helga (Autodesk Fusion 360 design; units mm, degrees)
Autodesk Fusion 360 part; units mm, degrees
note: some values were not read from the file. Set by a fixed rule: which sketch regions a step uses.
sketch "Sketch1" plane through (0, 0, 0) normal (0, 1, 0) x (1, 0, 0)
  line L0 (-18.8529, -6.608) -> (-18.8529, 6.7072)
  line L1 (-18.8529, 6.7072) -> (-13.5404, 6.7072)
  line L2 (-13.5404, 6.7072) -> (-13.5404, 9.306)
  line L3 (-13.5404, 9.306) -> (-10.8692, 9.306)
  line L4 (-10.8692, 9.306) -> (-10.8692, 14.6796)
  line L5 (-10.8692, 14.6796) -> (-8.1875, 14.6796)
  line L6 (-8.1875, 14.6796) -> (-8.1875, 17.4084)
  line L7 (-8.1875, 17.4084) -> (-2.8745, 17.4084)
  line L8 (-2.8745, 17.4084) -> (-2.8745, 20.1089)
  line L9 (-2.8745, 20.1089) -> (13.211, 20.1089)
  line L10 (13.211, 20.1089) -> (13.211, 17.4084)
  line L11 (21.2891, -9.3556) -> (21.2891, -12.059)
  line L12 (21.2891, -12.059) -> (18.5792, -12.059)
  line L13 (18.5792, -12.059) -> (18.5792, -14.682)
  line L14 (18.5792, -14.682) -> (15.9015, -14.682)
  line L15 (15.9015, -14.682) -> (15.9015, -17.4193)
  line L16 (15.9015, -17.4193) -> (13.2066, -17.4193)
  line L17 (-2.8389, -17.4193) -> (-8.1595, -17.4193)
  line L18 (-10.8692, 9.306) -> (-10.8657, -14.7405)
  line L19 (-18.8529, -6.608) -> (23.8924, -6.608)
  line L20 (-13.5404, 6.7072) -> (-13.5404, -9.665)
  line L21 (21.2891, -9.3556) -> (-13.5404, -9.3556)
  line L22 (18.5792, -12.059) -> (-10.8661, -12.059)
  line L23 (15.9015, -14.682) -> (-15.6391, -14.682)
  line L24 (13.2066, -17.4193) -> (-2.8389, -17.4193)
  line L25 (-8.1875, 14.6796) -> (-8.1875, -20.5391)
  line L26 (21.2891, -9.3556) -> (21.2891, 15.6129)
  line L27 (18.5792, -12.059) -> (18.5792, 18)
  line L28 (-8.1875, 14.6796) -> (23.3304, 14.6796)
  line L29 (-2.8745, 17.4084) -> (23.633, 17.4084)
  line L30 (15.9015, -14.682) -> (15.9015, 21.5634)
  line L31 (13.2066, -17.4193) -> (13.211, 17.4084)
  line L32 (-2.8745, 17.4084) -> (-2.8745, -22)
  line L33 (13.2066, -17.4193) -> (13.2088, -20.0387)
  line L34 (13.2088, -20.0387) -> (-3.2969, -20.0524)
  line L35 (21.2891, -9.3556) -> (23.9084, -9.3556)
  line L36 (-10.8692, 9.306) -> (27.1159, 9.306)
  line L37 (23.9084, -9.3556) -> (23.9084, 10.661)
  line L38 (21.2891, 12.0886) -> (-11.4104, 12.0886)
  line L39 (-13.5404, 6.7072) -> (25.3004, 6.7072)
  line L40 (-18.8529, -3.9765) -> (23.9084, -3.9765)
  line L41 (-16.2077, -1.3461) -> (-18.8529, -1.3461)
  line L42 (-16.2077, -1.3461) -> (25.3213, -1.3461)
  line L43 (-16.166, 1.3788) -> (-18.8529, 1.3788)
  line L44 (-16.166, 1.3788) -> (24.817, 1.3788)
  line L45 (-16.144, 3.9482) -> (-18.8529, 3.9482)
  line L46 (-16.144, 3.9482) -> (24.3622, 3.9482)
  line L47 (-16.144, 3.9482) -> (-16.144, 7.2291)
  line L48 (-16.144, 3.9482) -> (-16.166, -6.9315)
  line L49 (0, 0) -> (0.0167, -20.0497)
  line L50 (0, 0) -> (0, 20.1089)
  line L51 (-5.4992, -17.4193) -> (-5.531, 17.4084)
  line L52 (2.5197, -6.608) -> (2.5309, -20.0476)
  line L53 (2.5197, -6.608) -> (2.5197, 20.1089)
  line L54 (2.5309, -20.0476) -> (5.3487, -20.0452)
  line L55 (5.3487, -20.0452) -> (5.3487, 20.1089)
  line L56 (5.3487, -20.0452) -> (8.2373, -20.0428)
  line L57 (8.2373, -20.0428) -> (8.2373, 20.1089)
  line L58 (10.5159, -3.9765) -> (10.5159, -20.0452)
  line L59 (10.5159, -3.9765) -> (10.5159, 20.1089)
  line L60 (-16.1654, -6.608) -> (-13.5404, -9.3556)
  line L61 (-13.5404, -9.3556) -> (-10.8661, -12.059)
  line L62 (-10.8657, -14.7405) -> (-8.1595, -17.4193)
  line L63 (-5.4992, -17.4193) -> (-5.4989, -17.6947)
  line L64 (-5.4992, -17.4193) -> (-2.8745, -20.0521)
  line L65 (13.2088, -20.0387) -> (15.9015, -17.4193)
  line L66 (15.9015, -17.4193) -> (18.5792, -14.682)
  line L67 (18.5792, -14.682) -> (21.2891, -12.059)
  line L68 (21.2891, -12.059) -> (23.9084, -9.3556)
  line L69 (23.9084, 9.306) -> (21.2891, 12.0886)
  line L70 (21.2891, 12.0886) -> (18.5792, 14.6796)
  line L71 (18.5792, 14.6796) -> (15.9015, 17.4084)
  line L72 (15.9015, 17.4084) -> (13.211, 20.1089)
  line L73 (-2.8745, 20.1089) -> (-5.531, 17.4084)
  line L74 (-8.1875, 17.4084) -> (-10.8692, 14.6796)
  line L75 (-10.8692, 12.0886) -> (-13.5404, 9.306)
  line L76 (-13.5404, 9.306) -> (-16.144, 6.7072)
  dimension "d6" = 31.5406
  constraint vertical L0
  constraint perpendicular L0 L1
  constraint perpendicular L1 L2
  constraint perpendicular L2 L3
  constraint perpendicular L3 L4
  constraint perpendicular L4 L5
  constraint perpendicular L5 L6
  constraint perpendicular L6 L7
  constraint perpendicular L7 L8
  constraint perpendicular L8 L9
  constraint perpendicular L9 L10
  constraint perpendicular L11 L12
  constraint perpendicular L12 L13
  constraint perpendicular L13 L14
  constraint perpendicular L14 L15
  constraint perpendicular L15 L16
  constraint perpendicular L19 L20
  constraint coincident L20 L21.end
  constraint perpendicular L20 L21
  constraint coincident L18 L22.end
  constraint perpendicular L13 L22
  constraint horizontal L23
  constraint perpendicular L17 L25
  constraint perpendicular L21 L26
  constraint perpendicular L26 L28
  constraint perpendicular L27 L29
  constraint perpendicular L29 L30
  constraint perpendicular L33 L34
  constraint perpendicular L26 L35
  constraint horizontal L36
  constraint perpendicular L36 L37
  constraint coincident L26 L38.start
  constraint perpendicular L4 L38
  constraint perpendicular L37 L39
  constraint coincident L0 L40.start
  constraint coincident L37 L40.end
  constraint perpendicular L37 L40
  constraint coincident L0 L41.end
  constraint perpendicular L0 L41
  constraint perpendicular L37 L42
  constraint coincident L0 L43.end
  constraint perpendicular L0 L43
  constraint perpendicular L37 L44
  constraint coincident L0 L45.end
  constraint perpendicular L0 L45
  constraint perpendicular L37 L46
  constraint perpendicular L1 L47
  constraint coincident L49.start L50.start
  constraint coincident L34 L49.end
  constraint perpendicular L34 L49
  constraint coincident L9 L50.end
  constraint perpendicular L9 L50
  constraint midpoint L17 L51.start
  constraint midpoint L7 L51.end
  constraint midpoint L19 L52.start
  constraint coincident L34 L52.end
  constraint perpendicular L34 L52
  constraint coincident L9 L53.end
  constraint perpendicular L9 L53
  constraint coincident L34 L54.end
  constraint coincident L9 L55.end
  constraint perpendicular L9 L55
  constraint coincident L34 L56.end
  constraint parallel L34 L56
  constraint coincident L9 L57.end
  constraint perpendicular L9 L57
  constraint coincident L40 L58.start
  constraint perpendicular L24 L58
  constraint coincident L9 L59.end
  constraint perpendicular L9 L59
  constraint coincident L48 L60.start
  constraint coincident L19 L60.start
  constraint coincident L34 L64.end
  constraint coincident L32 L64.end
  constraint coincident L36 L69.start
  constraint coincident L37 L69.start
  constraint coincident L28 L70.end
  constraint coincident L27 L70.end
  constraint coincident L30 L71.end
  constraint coincident L29 L71.end
  constraint coincident L4 L75.start
  constraint coincident L38 L75.start
  constraint coincident L47 L76.end
  constraint coincident L1 L76.end
  measures "d6" distance of L14.end L23.end
extrude "Extrude1" add sketch "Sketch1" along normal blind 5 contours L0 L19 L40 L48 | L0 L40 L41 L42 L48 | L19 L20 L40 L48 | L19 L20 L60 | L0 L41 L42 L43 L44 L48 | L18 L19 L20 L40 | L18 L19 L20 L21 | L18 L21 L61 | L0 L43 L44 L45 L48 | L20 L42 L44 L48 | L18 L21 L22 L25 | L18 L22 L23 L25 | L0 L1 L45 L47 | L18 L20 L42 L44 | L18 L23 L25 L62 | L1 L20 L46 L47 | L17 L23 L25 L51 L62 | L1 L2 L76 | L18 L20 L39 L46 | L17 L23 L32 L51 | L2 L3 L18 L39 | L3 L4 L75 | L17 L32 L64 | L4 L25 L36 L38 | L4 L5 L25 L38 | L40 L42 L49 L53 | L19 L40 L53 L55 | L17 L24 L32 L34 L49 | L5 L6 L74 | L42 L44 L49 L50 L53 | L40 L42 L53 L55 | L19 L40 L55 L57 | L24 L34 L49 L52 | L6 L7 L28 L51 | L44 L46 L50 L53 | L42 L44 L53 L55 | L40 L42 L55 L57 | L19 L40 L57 L58 | L24 L34 L52 L54 L55 | L7 L28 L32 L51 | L7 L8 L73 | L44 L46 L53 L55 | L42 L44 L55 L57 | L40 L42 L57 L59 | L19 L31 L40 L58 | L19 L21 L31 L58 | L21 L22 L31 L58 | L24 L34 L55 L56 L57 | L8 L9 L29 L50 | L39 L46 L53 L55 | L44 L46 L55 L57 | L42 L44 L57 L59 | L19 L30 L31 L40 | L24 L34 L57 L58 | L9 L29 L50 L53 | L39 L46 L55 L57 | L44 L46 L57 L59 | L31 L42 L44 L59 | L30 L31 L40 L42 | L15 L16 L23 L31 | L24 L33 L34 L58 | L13 L14 L22 L30 | L9 L29 L53 L55 | L39 L46 L57 L59 | L30 L31 L42 L44 | L11 L12 L21 L27 | L14 L15 L66 | L16 L33 L65 | L12 L13 L67 | L9 L29 L55 L57 | L31 L39 L46 L59 | L30 L31 L44 L46 | L26 L35 L37 L40 | L11 L35 L68 | L31 L36 L39 L59 | L31 L36 L38 L59 | L9 L29 L57 L59 | L30 L31 L39 L46 | L26 L37 L40 L42 | L9 L10 L29 L59 | L26 L37 L42 L44 | L28 L29 L30 L31 | L10 L29 L72 | L27 L28 L30 L38 | L26 L37 L44 L46 | L26 L27 L36 L38 | L28 L30 L71 | L27 L38 L70 | L26 L37 L39 L46 | L26 L36 L37 L39 | L26 L36 L69 makes body 1 at (-13.5244, 0, 6.6467) makes body 2 at (5.1851, 0, 0.4581)
sketch "Sketch2" plane through (0, 5, 0) normal (0, 1, 0) x (-1, 0, 0)
  line L0 (10.8684, -3.9482) -> (10.8692, -9.306)
  line L1 (10.8692, -9.306) -> (8.1875, -9.306)
  line L2 (8.1875, -9.306) -> (8.1875, -14.6796)
  line L3 (8.1875, -14.6796) -> (2.8745, -14.6796)
  line L4 (2.8745, -14.6796) -> (2.8745, -17.4084)
  line L5 (2.8745, -17.4084) -> (-13.211, -17.4084)
  line L6 (-13.211, -17.4084) -> (-13.2106, -14.6796)
  line L7 (-13.2106, -14.6796) -> (-15.9015, -14.6796)
  line L8 (-15.9015, -14.6796) -> (-15.9015, -12.0886)
  line L9 (-15.9015, -12.0886) -> (-18.5792, -12.0886)
  line L10 (-18.5792, -12.0886) -> (-18.5792, -9.306)
  line L11 (-18.5792, -9.306) -> (-21.2891, -9.306)
  line L12 (-21.2891, -9.306) -> (-21.2891, 9.3556)
  line L13 (-21.2891, 9.3556) -> (-18.5792, 9.3556)
  line L14 (-18.5792, 9.3556) -> (-18.5792, 12.059)
  line L15 (-18.5792, 12.059) -> (-15.9015, 12.059)
  line L16 (-15.9015, 12.059) -> (-15.9015, 14.682)
  line L17 (-15.9015, 14.682) -> (-13.207, 14.682)
  line L18 (-13.207, 14.682) -> (-13.2066, 17.4193)
  line L19 (-13.2066, 17.4193) -> (2.8745, 17.4193)
  line L20 (2.8745, 17.4193) -> (2.8745, 14.682)
  line L21 (2.8745, 14.682) -> (8.1875, 14.682)
  line L22 (8.1875, 14.682) -> (8.1875, 9.3556)
  line L23 (8.1875, 9.3556) -> (10.8665, 9.3556)
  line L24 (10.8665, 9.3556) -> (10.8673, 3.9765)
  line L25 (10.8673, 3.9765) -> (16.16, 3.9765)
  line L26 (16.16, 3.9765) -> (16.1547, 1.3461)
  line L27 (16.1547, 1.3461) -> (10.8676, 1.3461)
  line L28 (10.8676, 1.3461) -> (10.868, -1.3788)
  line L29 (10.868, -1.3788) -> (16.1492, -1.3788)
  line L30 (16.1492, -1.3788) -> (16.144, -3.9482)
  line L31 (16.144, -3.9482) -> (10.8684, -3.9482)
  line L32 (10.8692, -12.0886) -> (13.5404, -9.306)
  line L33 (13.5404, -9.306) -> (16.144, -6.7072)
  line L34 (16.144, -6.7072) -> (18.8529, -6.7072)
  line L35 (18.8529, -6.7072) -> (18.8529, 6.608)
  line L36 (18.8529, 6.608) -> (16.1654, 6.608)
  line L37 (16.1654, 6.608) -> (13.5404, 9.3556)
  line L38 (13.5404, 9.3556) -> (10.8661, 12.059)
  line L39 (10.8661, 12.059) -> (10.8657, 14.7405)
  line L40 (10.8657, 14.7405) -> (8.1595, 17.4193)
  line L41 (8.1595, 17.4193) -> (5.4992, 17.4193)
  line L42 (5.4992, 17.4193) -> (2.8745, 20.0521)
  line L43 (2.8745, 20.0521) -> (-13.2088, 20.0387)
  line L44 (-13.2088, 20.0387) -> (-15.9015, 17.4193)
  line L45 (-15.9015, 17.4193) -> (-18.5792, 14.682)
  line L46 (-18.5792, 14.682) -> (-21.2891, 12.059)
  line L47 (-21.2891, 12.059) -> (-23.9084, 9.3556)
  line L48 (-23.9084, 9.3556) -> (-23.9084, -9.306)
  line L49 (-23.9084, -9.306) -> (-21.2891, -12.0886)
  line L50 (-21.2891, -12.0886) -> (-18.5792, -14.6796)
  line L51 (-18.5792, -14.6796) -> (-15.9015, -17.4084)
  line L52 (-15.9015, -17.4084) -> (-13.211, -20.1089)
  line L53 (-13.211, -20.1089) -> (2.8745, -20.1089)
  line L54 (2.8745, -20.1089) -> (5.531, -17.4084)
  line L55 (5.531, -17.4084) -> (8.1875, -17.4084)
  line L56 (8.1875, -17.4084) -> (10.8692, -14.6796)
  line L57 (10.8692, -14.6796) -> (10.8692, -12.0886)
  line L58 (18.8529, -6.7072) -> (16.144, -6.7072)
  line L59 (16.144, -6.7072) -> (10.8692, -12.0886)
  line L60 (10.8692, -12.0886) -> (10.8692, -14.6796)
  line L61 (10.8692, -14.6796) -> (8.1875, -17.4084)
  line L62 (8.1875, -17.4084) -> (5.531, -17.4084)
  line L63 (5.531, -17.4084) -> (2.8745, -20.1089)
  line L64 (2.8745, -20.1089) -> (-13.211, -20.1089)
  line L65 (-13.211, -20.1089) -> (-23.9084, -9.306)
  line L66 (-23.9084, -9.306) -> (-23.9084, 9.3556)
  line L67 (-23.9084, 9.3556) -> (-13.2088, 20.0387)
  line L68 (-13.2088, 20.0387) -> (2.8745, 20.0521)
  line L69 (2.8745, 20.0521) -> (5.4992, 17.4193)
  line L70 (5.4992, 17.4193) -> (8.1595, 17.4193)
  line L71 (10.8657, 14.7405) -> (8.1595, 17.4193)
  line L72 (10.8657, 14.7405) -> (10.8661, 12.059)
  line L73 (10.8661, 12.059) -> (16.1654, 6.608)
  line L74 (16.1654, 6.608) -> (18.8529, 6.608)
  line L75 (18.8529, 6.608) -> (18.8529, -6.7072)
  constraint coincident L34.end L35.start
  constraint coincident L33.end L34.start
  constraint coincident L32.start L57.end
  constraint coincident L56.end L57.start
  constraint coincident L55.end L56.start
  constraint coincident L54.end L55.start
  constraint coincident L53.end L54.start
  constraint coincident L52.end L53.start
  constraint coincident L48.end L49.start
  constraint coincident L47.end L48.start
  constraint coincident L43.end L44.start
  constraint coincident L42.end L43.start
  constraint coincident L41.end L42.start
  constraint coincident L40.end L41.start
  constraint coincident L39.end L40.start
  constraint coincident L38.end L39.start
  constraint coincident L36.end L37.start
  constraint coincident L35.end L36.start
sketch "Sketch3" plane through (0, 0, -3.9482) normal (0, 0, 1) x (1, 0, 0)
  line L0 (10.5159, 0) -> (13.2093, 0)
  line L1 (13.2093, 0) -> (13.2093, 5)
  line L2 (13.2093, 5) -> (10.5159, 5)
  line L3 (10.5159, 5) -> (10.5159, 0)
extrude "Extrude2" cut sketch "Sketch3" along normal blind 0.7 bodies 2
sketch "Sketch4" plane through (0, 0, 0) normal (0, -1, 0) x (1, 0, 0)
  line L0 (13.2093, -3.2482) -> (13.2093, -3.9482)
  line L1 (13.2093, -3.9482) -> (10.5159, -3.9482)
  line L2 (10.5159, -3.9482) -> (10.5159, -1.3788)
  line L3 (10.5159, -1.3788) -> (13.209, -1.3788)
  line L4 (13.209, -1.3788) -> (13.2092, -3.2482)
  line L5 (13.2092, -3.2482) -> (13.2093, -3.2482)
  line L6 (13.2083, 3.9765) -> (13.2086, 1.3461)
  line L7 (13.2086, 1.3461) -> (10.5159, 1.3461)
  line L8 (10.5159, 1.3461) -> (10.5159, 3.9765)
  line L9 (10.5159, 3.9765) -> (13.2083, 3.9765)
  line L10 (0.0033, 3.9765) -> (0, 0)
  line L11 (0, 0) -> (0, -3.9482)
  line L12 (0, -3.9482) -> (2.5197, -3.9482)
  line L13 (2.5197, -3.9482) -> (2.5197, -6.7072)
  line L14 (2.5197, -6.7072) -> (10.5159, -6.7072)
  line L15 (10.5159, -6.7072) -> (10.5159, -12.0886)
  line L16 (10.5159, -12.0886) -> (13.2103, -12.0886)
  line L17 (13.2103, -12.0886) -> (13.2096, -6.7072)
  line L18 (13.2096, -6.7072) -> (15.9015, -6.7072)
  line L19 (15.9015, -6.7072) -> (15.9015, 6.608)
  line L20 (15.9015, 6.608) -> (13.208, 6.608)
  line L21 (13.208, 6.608) -> (13.2073, 12.059)
  line L22 (13.2073, 12.059) -> (10.5159, 12.059)
  line L23 (10.5159, 12.059) -> (10.5159, 6.608)
  line L24 (10.5159, 6.608) -> (2.5197, 6.608)
  line L25 (2.5197, 6.608) -> (2.5197, 3.9765)
  line L26 (2.5197, 3.9765) -> (0.0033, 3.9765)
  line L27 (11.8621, 3.9765) -> (11.8623, 1.3461)
  line L28 (10.5159, 2.6613) -> (13.2085, 2.6613)
  line L29 (10.5159, -2.6635) -> (13.2091, -2.6486)
  line L30 (11.8625, -1.3788) -> (11.8626, -3.9482)
  line L31 (14.3625, -4.6561) -> (9.3625, -4.6561)
  line L32 (9.3625, -4.6561) -> (9.3625, -0.6561)
  line L33 (9.3625, -0.6561) -> (14.3625, -0.6561)
  line L34 (14.3625, -0.6561) -> (14.3625, -4.6561)
  line L35 (14.3625, -4.6561) -> (9.3625, -0.6561) construction
  line L36 (9.3625, -4.6561) -> (14.3625, -0.6561) construction
  line L37 (14.3622, 0.6613) -> (9.3622, 0.6613)
  line L38 (9.3622, 0.6613) -> (9.3622, 4.6613)
  line L39 (9.3622, 4.6613) -> (14.3622, 4.6613)
  line L40 (14.3622, 4.6613) -> (14.3622, 0.6613)
  line L41 (14.3622, 0.6613) -> (9.3622, 4.6613) construction
  line L42 (9.3622, 0.6613) -> (14.3622, 4.6613) construction
  point P0 (11.8625, -2.6561)
  point P1 (11.8622, 2.6613)
  point P2 (11.8625, -2.6561)
  point P3 (11.8622, 2.6613)
  dimension "d22" = 5
  dimension "d23" = 4
  dimension "d24" = 5
  dimension "d25" = 4
  constraint midpoint L9 L27.start
  constraint midpoint L7 L27.end
  constraint midpoint L8 L28.start
  constraint midpoint L6 L28.end
  constraint midpoint L2 L29.start
  constraint coincident L4 L29.end
  constraint midpoint L3 L30.start
  constraint midpoint L1 L30.end
  constraint midpoint L29 P2
  constraint midpoint L27 P3
  constraint perpendicular L31 L32
  constraint parallel L31 L33
  constraint parallel L32 L34
  constraint horizontal L31
  constraint coincident L35 P2
  constraint coincident L36 P2
  constraint coincident P2 P0
  constraint perpendicular L37 L38
  constraint parallel L37 L39
  constraint parallel L38 L40
  constraint horizontal L37
  constraint coincident L41 P3
  constraint coincident L42 P3
  constraint coincident P3 P1
  measures "d22" distance of L32.end L33.end
  measures "d23" distance of L31.end L32.end
  measures "d24" distance of L38.end L39.end
  measures "d25" distance of L37.end L38.end
sketch "Sketch5" plane through (0, 5, 0) normal (0, 1, 0) x (-1, 0, 0)
  line L0 (-13.2093, -3.2482) -> (-13.2092, -3.2482)
  line L1 (-13.2092, -3.2482) -> (-13.209, -1.3788)
  line L2 (-13.209, -1.3788) -> (-10.5159, -1.3788)
  line L3 (-10.5159, -1.3788) -> (-10.5159, -3.9482)
  line L4 (-10.5159, -3.9482) -> (-13.2093, -3.9482)
  line L5 (-13.2093, -3.9482) -> (-13.2093, -3.2482)
  line L6 (-13.2086, 1.3461) -> (-13.2083, 3.9765)
  line L7 (-13.2083, 3.9765) -> (-10.5159, 3.9765)
  line L8 (-10.5159, 3.9765) -> (-10.5159, 1.3461)
  line L9 (-10.5159, 1.3461) -> (-13.2086, 1.3461)
  line L10 (0, 0) -> (-0.0033, 3.9765)
  line L11 (-0.0033, 3.9765) -> (-2.5197, 3.9765)
  line L12 (-2.5197, 3.9765) -> (-2.5197, 6.608)
  line L13 (-2.5197, 6.608) -> (-10.5159, 6.608)
  line L14 (-10.5159, 6.608) -> (-10.5159, 12.059)
  line L15 (-10.5159, 12.059) -> (-13.2073, 12.059)
  line L16 (-13.2073, 12.059) -> (-13.208, 6.608)
  line L17 (-13.208, 6.608) -> (-15.9015, 6.608)
  line L18 (-15.9015, 6.608) -> (-15.9015, -6.7072)
  line L19 (-15.9015, -6.7072) -> (-13.2096, -6.7072)
  line L20 (-13.2096, -6.7072) -> (-13.2103, -12.0886)
  line L21 (-13.2103, -12.0886) -> (-10.5159, -12.0886)
  line L22 (-10.5159, -12.0886) -> (-10.5159, -6.7072)
  line L23 (-10.5159, -6.7072) -> (-2.5197, -6.7072)
  line L24 (-2.5197, -6.7072) -> (-2.5197, -3.9482)
  line L25 (-2.5197, -3.9482) -> (0, -3.9482)
  line L26 (0, -3.9482) -> (0, 0)
loft "Loft1" cut profiles "Sketch5", "Sketch4" section 1 contours L1 L2 L3 L4 L5 section 2 contours L0 L1 L4 L29 L30 | L3 L4 L29 L30 | L1 L2 L29 L30 | L2 L3 L29 L30 | L31 L32 L33 L34 bodies 2
loft "Loft2" cut profiles "Sketch5", "Sketch4" section 1 contours L6 L7 L8 L9 section 2 contours L6 L9 L27 L28 | L6 L7 L27 L28 | L8 L9 L27 L28 | L7 L8 L27 L28 | L37 L38 L39 L40 bodies 2
sketch "Sketch6" plane through (0, 0, 0) normal (0, -1, 0) x (1, 0, 0)
  line L0 (-13.5404, -9.306) -> (-10.8692, -12.0886)
  line L1 (-10.8692, -12.0886) -> (-10.8692, -14.6796)
  line L2 (-10.8692, -14.6796) -> (-8.1875, -17.4084)
  line L3 (-8.1875, -17.4084) -> (-5.531, -17.4084)
  line L4 (-5.531, -17.4084) -> (-2.8745, -20.1089)
  line L5 (-2.8745, -20.1089) -> (13.211, -20.1089)
  line L6 (13.211, -20.1089) -> (15.9015, -17.4084)
  line L7 (15.9015, -17.4084) -> (18.5792, -14.6796)
  line L8 (18.5792, -14.6796) -> (21.2891, -12.0886)
  line L9 (21.2891, -12.0886) -> (23.9084, -9.306)
  line L10 (23.9084, 9.3556) -> (21.2891, 12.059)
  line L11 (21.2891, 12.059) -> (18.5792, 14.682)
  line L12 (18.5792, 14.682) -> (15.9015, 17.4193)
  line L13 (15.9015, 17.4193) -> (13.2088, 20.0387)
  line L14 (13.2088, 20.0387) -> (-2.8745, 20.0521)
  line L15 (-2.8745, 20.0521) -> (-5.4992, 17.4193)
  line L16 (-5.4992, 17.4193) -> (-8.1595, 17.4193)
  line L17 (-8.1595, 17.4193) -> (-10.8657, 14.7405)
  line L18 (-10.8657, 14.7405) -> (-10.8661, 12.059)
  line L19 (-10.8661, 12.059) -> (-13.5404, 9.3556)
  line L20 (-13.5404, 9.3556) -> (-16.1654, 6.608)
  line L21 (-16.1654, 6.608) -> (-18.8529, 6.608)
  line L22 (-18.8529, -6.7072) -> (-16.144, -6.7072)
  line L23 (-16.144, -6.7072) -> (-13.5404, -9.306)
  line L24 (-18.8529, 6.608) -> (-16.1654, 6.608)
  line L25 (-16.1654, 6.608) -> (-10.8661, 12.059)
  line L26 (-10.8661, 12.059) -> (-10.8657, 14.7405)
  line L27 (-10.8657, 14.7405) -> (-8.1595, 17.4193)
  line L28 (-8.1595, 17.4193) -> (-5.4992, 17.4193)
  line L29 (-5.4992, 17.4193) -> (-2.8745, 20.0521)
  line L30 (-2.8745, 20.0521) -> (13.2088, 20.0387)
  line L31 (13.2088, 20.0387) -> (23.9084, 9.3556)
  line L32 (23.9084, -9.306) -> (13.211, -20.1089)
  line L33 (13.211, -20.1089) -> (-2.8745, -20.1089)
  line L34 (-2.8745, -20.1089) -> (-5.531, -17.4084)
  line L35 (-5.531, -17.4084) -> (-8.1875, -17.4084)
  line L36 (-8.1875, -17.4084) -> (-10.8692, -14.6796)
  line L37 (-10.8692, -14.6796) -> (-10.8692, -12.0886)
  line L38 (-10.8692, -12.0886) -> (-16.144, -6.7072)
  line L39 (-16.144, -6.7072) -> (-18.8529, -6.7072)
  line L40 (9.8625, -1.1561) -> (9.8625, -4.1561)
  line L41 (9.8625, -4.1561) -> (13.8625, -4.1561)
  line L42 (13.8625, -4.1561) -> (13.8625, -1.1561)
  line L43 (13.8625, -1.1561) -> (9.8625, -1.1561)
  line L44 (9.8622, 4.1613) -> (9.8622, 1.1613)
  line L45 (9.8622, 1.1613) -> (13.8622, 1.1613)
  line L46 (13.8622, 1.1613) -> (13.8622, 4.1613)
  line L47 (13.8622, 4.1613) -> (9.8622, 4.1613)
  line L48 (23.9084, 9.3556) -> (33.9084, 9.3556)
  line L49 (33.9084, 9.3556) -> (33.9084, -9.306)
  line L50 (33.9084, -9.306) -> (23.9084, -9.306)
  line L51 (-18.8529, 6.608) -> (-28.8529, 6.608)
  line L52 (-18.8529, -6.7072) -> (-28.8529, -6.7072)
  line L53 (-28.8529, 6.608) -> (-28.8529, -6.7072)
  point P0 (9.8625, -1.1561)
  point P1 (9.8625, -4.1561)
  point P2 (13.8625, -4.1561)
  point P3 (13.8625, -4.1561)
  point P4 (13.8625, -1.1561)
  point P5 (9.8622, 4.1613)
  point P6 (9.8622, 1.1613)
  point P7 (13.8622, 1.1613)
  point P8 (13.8622, 4.1613)
  dimension "d17" = 10
  dimension "d20" = 10
  dimension "d21" = 10
  constraint coincident L21.end L24.start
  constraint coincident L20.end L21.start
  constraint coincident L18.end L19.start
  constraint coincident L17.end L18.start
  constraint coincident L16.end L17.start
  constraint coincident L15.end L16.start
  constraint coincident L14.end L15.start
  constraint coincident L13.end L14.start
  constraint coincident L10.start L31.end
  constraint coincident L9.end L32.start
  constraint coincident L5.end L6.start
  constraint coincident L4.end L5.start
  constraint coincident L3.end L4.start
  constraint coincident L2.end L3.start
  constraint coincident L1.end L2.start
  constraint coincident L0.end L1.start
  constraint coincident L22.end L23.start
  constraint coincident L22.start L39.end
  constraint coincident P0 L40.start
  constraint coincident P1 L40.end
  constraint coincident P3 P2
  constraint coincident P4 L42.end
  constraint coincident P5 L44.start
  constraint coincident P6 L44.end
  constraint coincident P7 L45.end
  constraint coincident P8 L46.end
  constraint horizontal L48
  constraint vertical L49
  constraint horizontal L50
  constraint horizontal L51
  constraint perpendicular L52 L53
  measures "d17" distance of L10.start L48.end
  measures "d20" distance of L21.end L51.end
  measures "d21" distance of L22.start L52.end
chamfer "Chamfer2" distance 0.7 angle 45 17 edges at (6.5178, 5, -6.7072) (2.5197, 5, -5.3277) (1.2599, 5, -3.9482) (0, 5, -1.9741) (0.0017, 5, 1.9883) (1.2615, 5, 3.9765) (2.5197, 5, 5.2922) (6.5178, 5, 6.608) (10.5159, 5, 9.3335) (11.8616, 5, 12.059) (13.2076, 5, 9.3335) (14.5547, 5, 6.608) (15.9015, 5, -0.0496) (14.5556, 5, -6.7072) (13.21, 5, -9.3979) (10.5159, 5, -9.3979) (11.8631, 5, -12.0886) on bodies 2
chamfer "Chamfer3" distance 0.7 angle 45 59 edges at (-14.8529, 5, 7.9818) (-12.2033, 5, 10.7073) (-10.8659, 5, 13.3998) (-9.5126, 5, 16.0799) (-6.8293, 5, 17.4193) (-4.1868, 5, 18.7357) (5.1672, 5, 20.0454) (14.5552, 5, 18.729) (17.2404, 5, 16.0506) (19.9341, 5, 13.3705) (22.5987, 5, 10.7073) (23.9084, 5, 0.0248) (22.5987, 5, -10.6973) (19.9341, 5, -13.3841) (17.2404, 5, -16.044) (13.2106, 2.5, -14.6796) (14.5562, 5, -18.7586) (5.1683, 5, -20.1089) (-4.2027, 5, -18.7586) (-6.8593, 5, -17.4084) (-9.5283, 5, -16.044) (-10.8692, 5, -13.3841) (-12.2048, 5, -10.6973) (-14.8422, 5, -8.0066) (-17.4984, 5, -6.7072) (-18.8529, 5, -0.0496) (-17.5091, 5, 6.608) (-13.5136, 5, 3.9765) (-16.1574, 5, 2.6613) (-13.5112, 5, 1.3461) (-10.8678, 5, -0.0164) (-13.5086, 5, -1.3788) (-16.1466, 5, -2.6635) (-13.5062, 5, -3.9482) (-10.8688, 5, -6.6271) (-9.5283, 5, -9.306) (-8.1875, 5, -11.9928) (-5.531, 5, -14.6796) (-2.8745, 5, -16.044) (5.1683, 5, -17.4084) (13.2108, 5, -16.044) (14.5561, 5, -14.6796) (15.9015, 5, -13.3841) (18.5792, 5, -10.6973) (17.2404, 5, -12.0886) (19.9341, 5, -9.306) (21.2891, 5, 0.0248) (19.9341, 5, 9.3556) (18.5792, 5, 10.7073) (17.2404, 5, 12.059) (15.9015, 5, 13.3705) (14.5542, 5, 14.682) (13.2068, 5, 16.0506) (5.1661, 5, 17.4193) (-2.8745, 5, 16.0506) (-5.531, 5, 14.682) (-8.1875, 5, 12.0188) (-9.527, 5, 9.3556) (-10.8669, 5, 6.6661) on bodies 1
equation "d10 = --0.7 mm"
